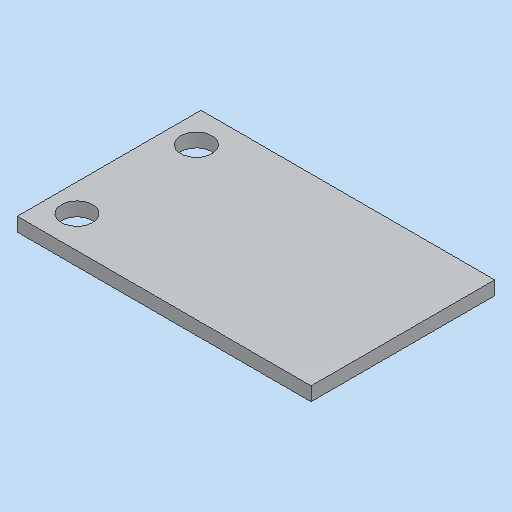
# Autodesk Inventor part: MM0948AN140_G01_102
Saved by Autodesk Inventor 2023.3 (Build 273359000, 359)
## iProperties
RuleStatus: InUse
Created: 2023-03-24
Part Number: MM0948AN140_G01_102
Material: 3.3206 AlMgSi0,5 - AW 6060
Description: =<RBPARTNOTITLE2>
Document SubType Name: Modeling
Designer: FH/Wi
Mass: 2.51846 g
Surface Area: 14.3173 cm^2
Volume: 0.932762 cm^3
Density: 2.7 g/cm^3
Appearance: Aluminium AnP
AnP_Kategorie: 1
AnP_Material: =<Material>
MaxAbmaße: 1,5 x 20 x 32 (FM)
AnP_TemplVers: 20200821
RBDOCUMENTTYPE: DRF
RBDOCUMENTVERSION: 00
RBDRAWINGMAINSCALE: 1:1
RBDRAWINGMISSINGSPEC: --
RBDRAWINGVOLUME: --
RBDSV1: 0850
RBGBEDGESIN1: +0,5
RBGBEDGESIN2: +0,2
RBGBEDGESOUT1: -0,3
RBGBEDGESOUT2: -0,1
RBMATERIAL: =<Material>
RBMATMEETS: --
RBMATNO: =<Part Number>
RBPARTMADEOF: 1,5 x 20 x 32 (FM)
RBPARTNO: SIEHE MNR
RBPARTNOTITLE1: manufactured part
RBPARTNOTITLE2: Anfertigungsteil
RBPARTSAFETYINDICATOR: --
RBSURFACE: anodised colourless
RBSURFACE2: eloxiert farblos
RBZEDGESNORM: ISO13715:2002-06
RBZGENDIMCLASS: m
RBZGENDIMNORM: ISO 2768-1:1989-11
RBZGENGEOCLASS: H
RBZGENGEONORM: ISO 2768-2:1989-11
RBZSURFACENORM: ISO13D2:2002-02
RBZTOLERANCENORM: ISO 14405-1:2010-12
Author: FH/Wi
Keywords: =<RBPARTMADEOF>
Comments: =<RBSURFACE2>
Revision Number: 01
Autodesk Inventor part; units mm, degrees
ref_plane "YZ Plane" through (0, 0, 0) normal (1, 0, 0) x (0, 1, 0)
ref_plane "XZ Plane" through (0, 0, 0) normal (0, 1, 0) x (-1, 0, 0)
ref_plane "XY Plane" through (0, 0, 0) normal (0, 0, 1) x (1, 0, 0)
sketch "Skizze1" plane through (0, 0, 0) normal (0, 0, 1) x (1, 0, 0)
  line L0 (0, 10) -> (32, 10)
  line L1 (32, 10) -> (32, -10)
  line L2 (32, -10) -> (0, -10)
  line L3 (0, -10) -> (0, 10)
  point P0 (0, 0)
  point P1 (0, 0)
  dimension "d0" = 32
  dimension "d1" = 20
  constraints: 8 end point, 2 parallel, 1 coincident, 1 horizontal, 1 midpoint, 1 perpendicular
  measures "d0" distance of L0.start L0.end
  measures "d1" distance of L2.end L0.start
extrude "Extrusion1" add sketch "Skizze1" along normal blind 1.5
sketch "Skizze2" plane through (0, 0, 1.5) normal (0, 0, 1) x (1, 0, 0)
  line L0 (32, -10) -> (32, 10) projected
  line L1 (32, 0) -> (19.2662, 0)
  point P0 (0, 0)
  point P1 (3, 6.5)
  point P2 (3, -6.5)
  dimension "d11" = 29
  dimension "d12" = 13
  constraints: 2 end point, 1 horizontal, 1 midpoint, 1 symmetric about line
  measures "d11" distance from line of L0 point (3, 6.5)
  measures "d12" distance of point (3, -6.5) point (3, 6.5)
hole "Bohrung1" at (3, 6.5, 1.5) at (3, -6.5, 1.5) direction (0, 0, -1) diameter 3.4 end through all clearance for "Inbusschraube ISO 4762  versenkt" size "M3" standard "ISO"
